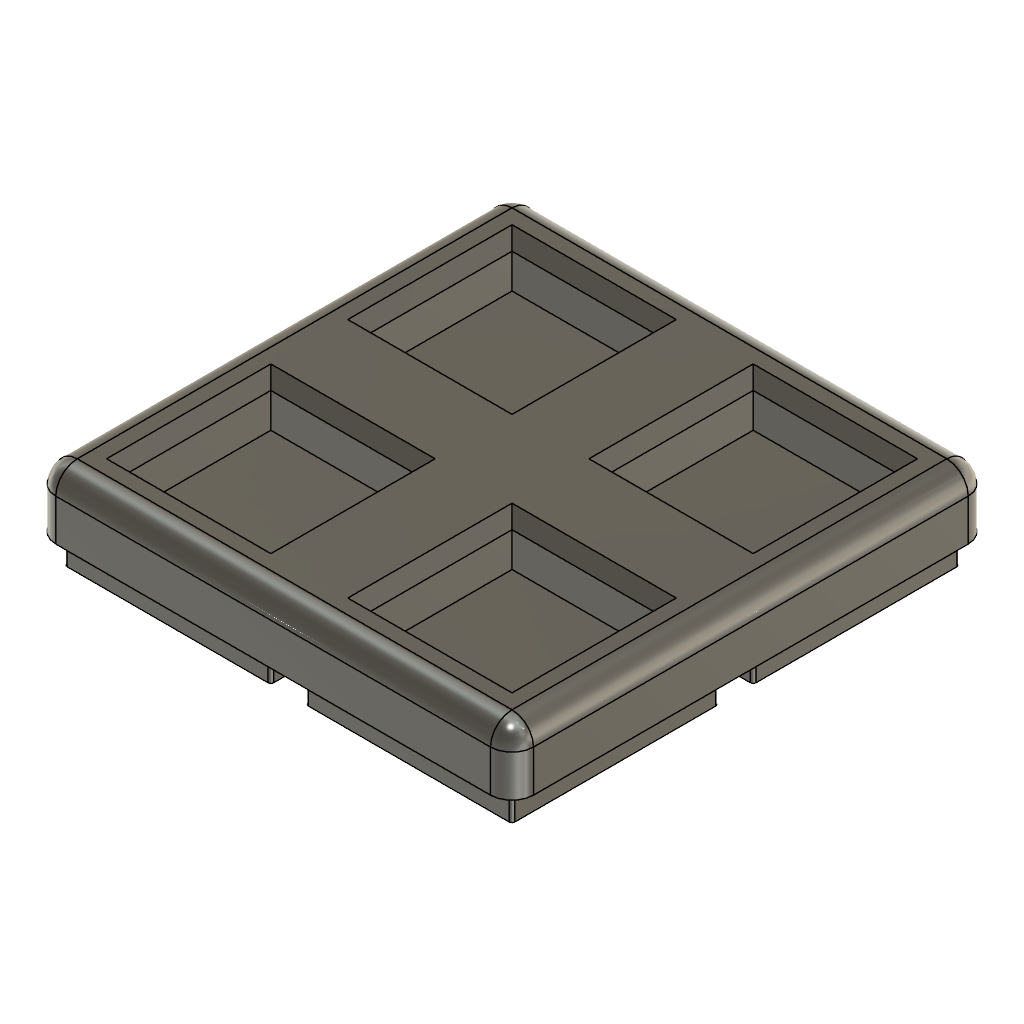
atoms3-input-holder-v1 (Autodesk Fusion 360 design; units mm, degrees)
part number: 2026-10-03-11-04-50-135
Autodesk Fusion 360 part; units mm, degrees
sketch "Sketch_OuterProfile" plane through (0, 0, 0) normal (0, 0, 1) x (1, 0, 0)
  line L0 (41.6, 41.6) -> (-41.6, 41.6)
  line L1 (-41.6, 41.6) -> (-41.6, -41.6)
  line L2 (-41.6, -41.6) -> (41.6, -41.6)
  line L3 (41.6, -41.6) -> (41.6, 41.6)
  dimension "d24" = 83.2
  dimension "d25" = 83.2
  measures "d24" horizontal distance of L0.start L0.end
  measures "d25" vertical distance of L0.end L1.end
extrude "Extrude_Body" add sketch "Sketch_OuterProfile" along normal blind 11
fillet "Fillet_OuterVerticalEdges" radius 3.75 4 edges at (41.6, -41.6, 5.5) (-41.6, -41.6, 5.5) (-41.6, 41.6, 5.5) (41.6, 41.6, 5.5)
fillet "Fillet_TopOuterEdge" radius 3.75 64 edges at (40.5017, 40.5017, 11) (41.6, 0, 11) (40.5017, -40.5017, 11) (0, -41.6, 11) (-40.5017, -40.5017, 11) (-41.6, 0, 11) (-40.5017, 40.5017, 11) (0, 41.6, 11) (0, 41.6, 11) (-40.5017, 40.5017, 11) (-41.6, 0, 11) (-40.5017, -40.5017, 11) (0, -41.6, 11) (40.5017, -40.5017, 11) (41.6, 0, 11) (40.5017, 40.5017, 11) (-40.5017, 40.5017, 11) (0, 41.6, 11) (40.5017, 40.5017, 11) (41.6, 0, 11) (40.5017, -40.5017, 11) (0, -41.6, 11) (-40.5017, -40.5017, 11) (-41.6, 0, 11) (-41.6, 0, 11) (-40.5017, -40.5017, 11) (0, -41.6, 11) (40.5017, -40.5017, 11) (41.6, 0, 11) (40.5017, 40.5017, 11) (0, 41.6, 11) (-40.5017, 40.5017, 11) (-40.5017, -40.5017, 11) (-41.6, 0, 11) (-40.5017, 40.5017, 11) (0, 41.6, 11) (40.5017, 40.5017, 11) (41.6, 0, 11) (40.5017, -40.5017, 11) (0, -41.6, 11) (0, -41.6, 11) (40.5017, -40.5017, 11) (41.6, 0, 11) (40.5017, 40.5017, 11) (0, 41.6, 11) (-40.5017, 40.5017, 11) (-41.6, 0, 11) (-40.5017, -40.5017, 11) (40.5017, -40.5017, 11) (0, -41.6, 11) (-40.5017, -40.5017, 11) (-41.6, 0, 11) (-40.5017, 40.5017, 11) (0, 41.6, 11) (40.5017, 40.5017, 11) (41.6, 0, 11) (41.6, 0, 11) (40.5017, 40.5017, 11) (0, 41.6, 11) (-40.5017, 40.5017, 11) (-41.6, 0, 11) (-40.5017, -40.5017, 11) (0, -41.6, 11) (40.5017, -40.5017, 11)
ref_plane "WorkPlane1" through (0, 0, 11) normal (0, 0, 1) x (1, 0, 0)
sketch "Sketch_Pocket_1" plane through (0, 0, 11) normal (0, 0, 1) x (1, 0, 0)
  line L0 (-8.7, -8.7) -> (-33.3, -8.7)
  line L1 (-33.3, -8.7) -> (-33.3, -33.3)
  line L2 (-33.3, -33.3) -> (-8.7, -33.3)
  line L3 (-8.7, -33.3) -> (-8.7, -8.7)
  dimension "d35" = 24.6
  dimension "d36" = 24.6
  measures "d35" horizontal distance of L0.start L0.end
  measures "d36" vertical distance of L0.end L1.end
extrude "Extrude_Pocket_1" cut sketch "Sketch_Pocket_1" against normal blind 8
sketch "Sketch_Pocket_2" plane through (0, 0, 11) normal (0, 0, 1) x (1, 0, 0)
  line L0 (-8.7, 33.3) -> (-33.3, 33.3)
  line L1 (-33.3, 33.3) -> (-33.3, 8.7)
  line L2 (-33.3, 8.7) -> (-8.7, 8.7)
  line L3 (-8.7, 8.7) -> (-8.7, 33.3)
  dimension "d39" = 24.6
  dimension "d40" = 24.6
  measures "d39" horizontal distance of L0.start L0.end
  measures "d40" vertical distance of L0.end L1.end
extrude "Extrude_Pocket_2" cut sketch "Sketch_Pocket_2" against normal blind 8
sketch "Sketch_Pocket_3" plane through (0, 0, 11) normal (0, 0, 1) x (1, 0, 0)
  line L0 (33.3, -8.7) -> (8.7, -8.7)
  line L1 (8.7, -8.7) -> (8.7, -33.3)
  line L2 (8.7, -33.3) -> (33.3, -33.3)
  line L3 (33.3, -33.3) -> (33.3, -8.7)
  dimension "d43" = 24.6
  dimension "d44" = 24.6
  measures "d43" horizontal distance of L0.start L0.end
  measures "d44" vertical distance of L0.end L1.end
extrude "Extrude_Pocket_3" cut sketch "Sketch_Pocket_3" against normal blind 8
sketch "Sketch_Pocket_4" plane through (0, 0, 11) normal (0, 0, 1) x (1, 0, 0)
  line L0 (33.3, 33.3) -> (8.7, 33.3)
  line L1 (8.7, 33.3) -> (8.7, 8.7)
  line L2 (8.7, 8.7) -> (33.3, 8.7)
  line L3 (33.3, 8.7) -> (33.3, 33.3)
  dimension "d47" = 24.6
  dimension "d48" = 24.6
  measures "d47" horizontal distance of L0.start L0.end
  measures "d48" vertical distance of L0.end L1.end
extrude "Extrude_Pocket_4" cut sketch "Sketch_Pocket_4" against normal blind 8
chamfer "Chamfer_PocketEdges" distance 2 angle 45 12 edges at (33.3, 21, 11) (8.7, 21, 11) (21, 33.3, 11) (33.3, -21, 11) (8.7, -21, 11) (21, -8.7, 11) (-8.7, 21, 11) (-33.3, 21, 11) (-21, 33.3, 11) (-8.7, -21, 11) (-33.3, -21, 11) (-21, -8.7, 11) tangent chain off
chamfer "Chamfer_PocketEdges" distance 2 angle 45 4 edges at (21, -33.3, 11) (-21, -33.3, 11) (-21, 8.7, 11) (21, 8.7, 11) tangent chain off
sketch "Sketch_Foot_1" plane through (0, 0, 0) normal (0, 0, 1) x (1, 0, 0)
  line L0 (-3.01, -3.01) -> (-38.99, -3.01)
  line L1 (-38.99, -3.01) -> (-38.99, -38.99)
  line L2 (-38.99, -38.99) -> (-3.01, -38.99)
  line L3 (-3.01, -38.99) -> (-3.01, -3.01)
  dimension "d61" = 35.98
  dimension "d62" = 35.98
  measures "d61" horizontal distance of L0.start L0.end
  measures "d62" vertical distance of L0.end L1.end
extrude "Extrude_Foot_1" add sketch "Sketch_Foot_1" against normal blind 4.65
fillet "Fillet_FootEdges_1" radius 0.5 4 edges at (-3.01, -3.01, -2.325) (-38.99, -3.01, -2.325) (-38.99, -38.99, -2.325) (-3.01, -38.99, -2.325)
sketch "Sketch_Foot_2" plane through (0, 0, 0) normal (0, 0, 1) x (1, 0, 0)
  line L0 (-3.01, 38.99) -> (-38.99, 38.99)
  line L1 (-38.99, 38.99) -> (-38.99, 3.01)
  line L2 (-38.99, 3.01) -> (-3.01, 3.01)
  line L3 (-3.01, 3.01) -> (-3.01, 38.99)
  dimension "d67" = 35.98
  dimension "d68" = 35.98
  measures "d67" horizontal distance of L0.start L0.end
  measures "d68" vertical distance of L0.end L1.end
extrude "Extrude_Foot_2" add sketch "Sketch_Foot_2" against normal blind 4.65
fillet "Fillet_FootEdges_2" radius 0.5 4 edges at (-3.01, 38.99, -2.325) (-38.99, 38.99, -2.325) (-38.99, 3.01, -2.325) (-3.01, 3.01, -2.325)
sketch "Sketch_Foot_3" plane through (0, 0, 0) normal (0, 0, 1) x (1, 0, 0)
  line L0 (38.99, -3.01) -> (3.01, -3.01)
  line L1 (3.01, -3.01) -> (3.01, -38.99)
  line L2 (3.01, -38.99) -> (38.99, -38.99)
  line L3 (38.99, -38.99) -> (38.99, -3.01)
  dimension "d73" = 35.98
  dimension "d74" = 35.98
  measures "d73" horizontal distance of L0.start L0.end
  measures "d74" vertical distance of L0.end L1.end
extrude "Extrude_Foot_3" add sketch "Sketch_Foot_3" against normal blind 4.65
fillet "Fillet_FootEdges_3" radius 0.5 4 edges at (38.99, -3.01, -2.325) (3.01, -3.01, -2.325) (3.01, -38.99, -2.325) (38.99, -38.99, -2.325)
sketch "Sketch_Foot_4" plane through (0, 0, 0) normal (0, 0, 1) x (1, 0, 0)
  line L0 (38.99, 38.99) -> (3.01, 38.99)
  line L1 (3.01, 38.99) -> (3.01, 3.01)
  line L2 (3.01, 3.01) -> (38.99, 3.01)
  line L3 (38.99, 3.01) -> (38.99, 38.99)
  dimension "d79" = 35.98
  dimension "d80" = 35.98
  measures "d79" horizontal distance of L0.start L0.end
  measures "d80" vertical distance of L0.end L1.end
extrude "Extrude_Foot_4" add sketch "Sketch_Foot_4" against normal blind 4.65
fillet "Fillet_FootEdges_4" radius 0.5 4 edges at (38.99, 38.99, -2.325) (3.01, 38.99, -2.325) (3.01, 3.01, -2.325) (38.99, 3.01, -2.325)
extrude "Extrude10" add 4 faces at (15.3367, -26.83, -4.65) (15.17, 15.3367, -4.65) (-26.83, 15.0033, -4.65) (-15.17, -26.9967, -4.65) along direction (0, 0, -1) blind 0.4
equation "grid_pitch = 42 mm" comment "Gridfinity grid pitch (standard, per MG400 rig doc)"
equation "grid_clearance = 0.3 mm" comment "Fit clearance measured in Lab 1 (range 0.2-0.4 mm, chosen 0.3 mm)"
equation "gf_outer_offset = 0.5 mm" comment "Standard Gridfinity outer undersize per cell (42n - 0.5)"
equation "gf_corner_radius = 3.75 mm" comment "Standard Gridfinity outer corner radius"
equation "gf_foot_chamfer_bottom = 0.8 mm" comment "Gridfinity foot: bottom 45deg segment height (reference)"
equation "gf_foot_vertical = 1.8 mm" comment "Gridfinity foot: vertical segment height (reference)"
equation "gf_foot_chamfer_top = 2.15 mm" comment "Gridfinity foot: top 45deg segment height (reference)"
equation "foot_lead_in_chamfer = gf_foot_chamfer_bottom + gf_foot_chamfer_top" comment "Simplified single lead-in chamfer approximating the Gridfinity foot flare"
equation "grid_cols = 2" comment "Number of Gridfinity cells in X (build-time layout parameter)"
equation "grid_rows = 2" comment "Number of Gridfinity cells in Y (build-time layout parameter)"
equation "atom_width = 24.0 mm" comment "M5Stack AtomS3 official width (SKU C123)"
equation "atom_length = 24.0 mm" comment "M5Stack AtomS3 official length (SKU C123)"
equation "atom_height = 12.9 mm" comment "M5Stack AtomS3 official height (SKU C123)"
equation "part_clearance = 0.3 mm" comment "Printer fit clearance measured in Lab 1, applied per side between AtomS3 and pocket"
equation "pocket_width = atom_width + 2 * part_clearance" comment "Pocket opening width (AtomS3 width plus clearance both sides)"
equation "pocket_length = atom_length + 2 * part_clearance" comment "Pocket opening length (AtomS3 length plus clearance both sides)"
equation "pocket_depth = 8 mm" comment "ASSUMPTION: pocket depth, not specified by user; leaves part protruding for grip/suction access"
equation "lead_in_chamfer = 1 mm" comment "Standard chamfer on 3 sides of each pocket opening, aids insertion"
equation "key_edge_chamfer = lead_in_chamfer * 2" comment "Larger chamfer on one marked edge of each pocket: orientation key + extra finger access"
equation "floor_thickness = 3 mm" comment "ASSUMPTION: solid floor thickness beneath pockets, not specified by user"
equation "holder_height = pocket_depth + floor_thickness" comment "Total external height of the holder"
equation "holder_outer_x = grid_pitch * grid_cols - gf_outer_offset - grid_clearance" comment "Outer footprint in X, derived from cell count"
equation "holder_outer_y = grid_pitch * grid_rows - gf_outer_offset - grid_clearance" comment "Outer footprint in Y, derived from cell count"
equation "d24 = holder_outer_x"
equation "d25 = holder_outer_y"
equation "d26 = holder_height"
equation "d29 = gf_corner_radius"
equation "d32 = gf_corner_radius"
equation "d33 = holder_height"
equation "d35 = pocket_width"
equation "d36 = pocket_length"
equation "d37 = -pocket_depth"
equation "d39 = pocket_width"
equation "d40 = pocket_length"
equation "d41 = -pocket_depth"
equation "d43 = pocket_width"
equation "d44 = pocket_length"
equation "d45 = -pocket_depth"
equation "d47 = pocket_width"
equation "d48 = pocket_length"
equation "d49 = -pocket_depth"
equation "gf_socket_mouth_size = 41.98 mm" comment "MEASURED from MG400 rakis grid_pos_0: top opening of real baseplate socket"
equation "gf_socket_mid_size = 37.68 mm" comment "MEASURED: socket width after top chamfer segment"
equation "gf_socket_floor_size = 36.28 mm" comment "MEASURED: narrowest width at socket floor"
equation "gf_socket_depth = 4.65 mm" comment "MEASURED: real socket depth (0.70 + 1.80 + 2.15 mm segments), corrects earlier 4.75 mm assumption"
equation "foot_size = gf_socket_floor_size - grid_clearance" comment "Simplified constant-width foot sized to the socket floor (narrowest, guaranteed-fit) minus clearance"
equation "foot_depth = gf_socket_depth" comment "Foot protrusion depth below the main floor, matches measured socket depth"
equation "foot_corner_radius = 0.5 mm" comment "MEASURED (approx): real socket corner radius near its narrowest point"
equation "total_height_with_feet = holder_height + foot_depth" comment "Overall height including protruding feet, for reference"
equation "d61 = foot_size"
equation "d62 = foot_size"
equation "d63 = -foot_depth"
equation "d66 = foot_corner_radius"
equation "d67 = foot_size"
equation "d68 = foot_size"
equation "d69 = -foot_depth"
equation "d72 = foot_corner_radius"
equation "d73 = foot_size"
equation "d74 = foot_size"
equation "d75 = -foot_depth"
equation "d78 = foot_corner_radius"
equation "d79 = foot_size"
equation "d80 = foot_size"
equation "d81 = -foot_depth"
equation "d84 = foot_corner_radius"
named bodies: "AtomS3HolderBody"
